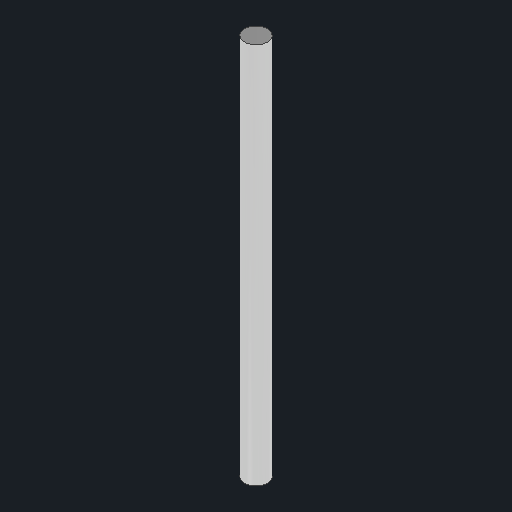
# Autodesk Inventor part: counterweight_bar
Saved by Autodesk Inventor 2027.1 (Build 311270010, 270A)
## iProperties
Created: 2026-11-04
Part Number: counterweight_bar
Material: Generic
Description: Counterweight bar, 19 mm (0.75 in)
Document SubType Name: Modeling
Designer: Claude (from photos)
Density: 1 g/cm^3
Appearance: Chrome - Polished
Author: alexg
Autodesk Inventor part; units mm, degrees
ref_plane "YZ Plane" through (0, 0, 0) normal (1, 0, 0) x (0, 1, 0)
ref_plane "XY Plane" through (0, 0, 0) normal (0, 0, 1) x (1, 0, 0)
ref_plane "Work Plane1" through (0, -135, 0) normal (0, 1, 0) x (-1, 0, 0)
sketch "Counterweight bar 19mm (0.75in) sketch" plane through (0, -135, 0) normal (0, 1, 0) x (-1, 0, 0)
  circle A0 centre (-187, 0) radius 9.5
  constraints: 1 centre point
extrude "Counterweight bar 19mm (0.75in)" add sketch "Counterweight bar 19mm (0.75in) sketch" against normal blind 315
body "Solid1"
